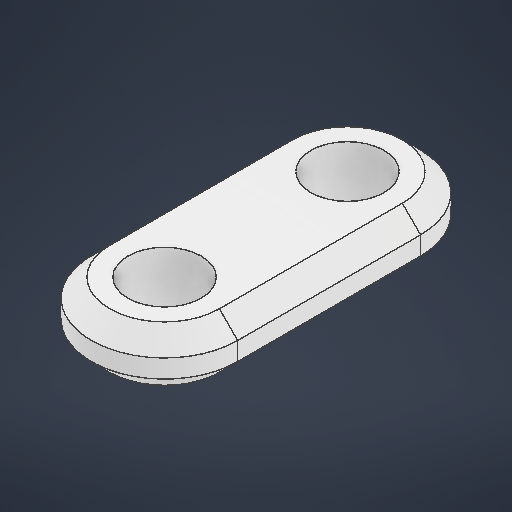
# Autodesk Inventor part: GT2 Timing Belt Fixation
Saved by Autodesk Inventor 2026.2 (Build 302298010, 298A)
## iProperties
Created: 2026-04-28
Part Number: GT2 Timing Belt Fixation
Material: ABS 플라스틱
Document SubType Name: Modeling
Designer: work
Density: 1.06 g/cm^3
Appearance: 매끄러움 - 흰색
Author: work
Autodesk Inventor part; units mm, degrees
ref_plane "YZ Plane" through (0, 0, 0) normal (1, 0, 0) x (0, 1, 0)
ref_plane "XZ Plane" through (0, 0, 0) normal (0, 1, 0) x (-1, 0, 0)
ref_plane "XY Plane" through (0, 0, 0) normal (0, 0, 1) x (1, 0, 0)
sketch "스케치1" plane through (0, 0, 0) normal (0, 1, 0) x (-1, 0, 0)
  line L0 (0, 0) -> (0, -10) construction
  line L1 (-4, 0) -> (-4, -10)
  line L2 (4, -10) -> (4, 0)
  arc A0 (4, 0) -> (-4, 0) centre (0, 0) ccw
  arc A1 (-4, -10) -> (4, -10) centre (0, -10) ccw
  circle A2 centre (0, 0) radius 2
  circle A3 centre (0, -10) radius 2
  point P0 (0, -5)
  dimension "d0" = 10
  dimension "d1" = 8
  dimension "d2" = 4
  dimension "d3" = 4
  constraints: 8 end point, 4 centre point, 4 point on circle, 4 tangent, 2 coincident, 1 midpoint, 1 parallel, 1 vertical
  measures "d0" distance of L0.start L0.end
  measures "d1" diameter of A1
  measures "d2" diameter of A2
  measures "d3" diameter of A3
extrude "돌출1" add sketch "스케치1" along normal blind 3
chamfer "모따기1" distance 1 angle 45 8 edges at (4, 3, -5) (0, 3, -14) (-4, 3, -5) (0, 3, 4) (4, 0, -5) (0, 0, -14) (-4, 0, -5) (0, 0, 4)
